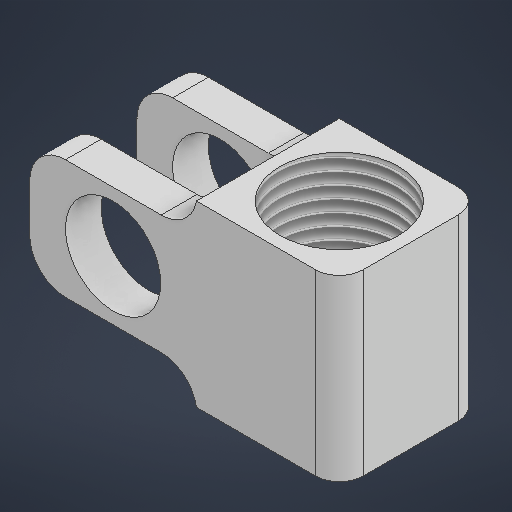
# Autodesk Inventor part: locomotive
Saved by Autodesk Inventor 2027.1 (Build 311270010, 270A)
## iProperties
Created: 2026-11-04
Part Number: locomotive
Material: Ogólny
Document SubType Name: Modeling
Designer: User
Density: 1 g/cm^3
Appearance: Domyślna
Author: User
Autodesk Inventor part; units mm, degrees
ref_plane "YZ Plane" through (0, 0, 0) normal (1, 0, 0) x (0, 1, 0)
ref_plane "XZ Plane" through (0, 0, 0) normal (0, 1, 0) x (-1, 0, 0)
sketch "Szkic1" plane through (0, 0, 0) normal (0, 1, 0) x (-1, 0, 0)
  circle A0 centre (0, 0) radius 5
  line L0 (-6, 6) -> (6, 6)
  line L1 (6, 6) -> (6, -6)
  line L2 (6, -6) -> (-6, -6)
  line L3 (-6, -6) -> (-6, 6)
  line L4 (-6, 6) -> (6, -6) construction
  line L5 (6, 6) -> (-6, -6) construction
  dimension "d0" = 10
  dimension "d1" = 12
  dimension "d2" = 12
  constraints: 12 end point, 2 midpoint, 2 parallel, 1 centre point, 1 coincident, 1 horizontal, 1 perpendicular
  measures "d0" diameter of A0
  measures "d1" distance of L1.end L2.end
  measures "d2" distance of L0.end L1.end
extrude "Wyciągnięcie proste1" add sketch "Szkic1" along normal blind 15
thread "Gwint1" size "M10x1" class "6H" standard "ANSI Metric M Profile" full length
ref_plane "Płaszczyzna konstrukcyjna1" through (0, 7.5, 0) normal (0, 1, 0) x (1, 0, 0)
sketch "Szkic2" plane through (0, 7.5, 0) normal (0, 1, 0) x (1, 0, 0)
  line L0 (-6, -6) -> (6, -6) projected
  line L1 (-6, -6) -> (-20, -6)
  line L2 (-6, -6) -> (8, -6) construction
  line L3 (-20, -6) -> (-20, -3)
  line L4 (-20, -3) -> (-6, -3)
  line L5 (-6, 6) -> (-6, -6) projected
  line L6 (-6, 0) -> (-15.4437, 0) construction
  line L7 (-6, -6) -> (-6, -3)
  line L8 (-6, 6) -> (-20, 6)
  line L9 (-6, 6) -> (8, 6) construction
  line L10 (-20, 6) -> (-20, 3)
  line L11 (-20, 3) -> (-6, 3)
  line L12 (-6, -6) -> (-6, 6)
  line L13 (-6, 6) -> (-6, 3)
  point P0 (0, 0)
  dimension "d8" = 14
  dimension "d9" = 180
  dimension "d10" = 3
  constraints: 24 end point, 6 symmetric about line, 3 horizontal, 2 collinear, 2 perpendicular, 1 midpoint
  measures "d8" distance of L0.start L1.end
  measures "d9" angle of L1 L2
  measures "d10" distance of L1.end L3.end
extrude "Wyciągnięcie proste2" add sketch "Szkic2" along normal mid plane 10
sketch "Szkic3" plane through (6, 0, -6) normal (0, 0, -1) x (-1, 0, 0)
  circle A0 centre (19, 7.5) radius 4
  line L0 (0, 0) -> (12, 0) projected
  line L1 (12, 0) -> (12, 2.5) projected
  line L2 (26, 2.5) -> (12, 2.5) projected
  line L3 (26, 2.5) -> (26, 12.5) projected
  line L4 (12, 12.5) -> (26, 12.5) projected
  line L5 (12, 12.5) -> (12, 15) projected
  line L6 (0, 15) -> (12, 15) projected
  line L7 (0, 0) -> (0, 15) projected
  line L8 (0, 0) -> (12, 0) projected
  line L9 (12, 0) -> (12, 2.5) projected
  line L10 (26, 2.5) -> (12, 2.5) projected
  line L11 (26, 2.5) -> (26, 12.5) projected
  line L12 (12, 12.5) -> (26, 12.5) projected
  line L13 (12, 12.5) -> (12, 15) projected
  line L14 (0, 15) -> (12, 15) projected
  line L15 (0, 0) -> (0, 15) projected
  line L16 (26, 2.5) -> (26, 12.5) projected
  line L17 (26, 12.5) -> (12, 2.5)
  line L18 (26, 2.5) -> (12, 12.5)
  point P0 (6, 0)
  dimension "d14" = 8
  constraints: 4 end point, 1 centre point, 1 coincident, 1 midpoint
  measures "d14" diameter of A0
extrude "Wyciągnięcie proste3" cut sketch "Szkic3" against normal blind 17 contours A0 L18 L17 | L17 L18 A0 | A0 L17 L18 | L18 L17 A0
fillet "Zaokrąglenie2" radius 3 8 edges at (-20, 12.5, -4.5) (-20, 12.5, 4.5) (-6, 12.5, 4.5) (-6, 12.5, -4.5) (-6, 2.5, -4.5) (-20, 2.5, -4.5) (-6, 2.5, 4.5) (-20, 2.5, 4.5)
fillet "Zaokrąglenie3" radius 2 2 edges at (6, 7.5, -6) (6, 7.5, 6)
